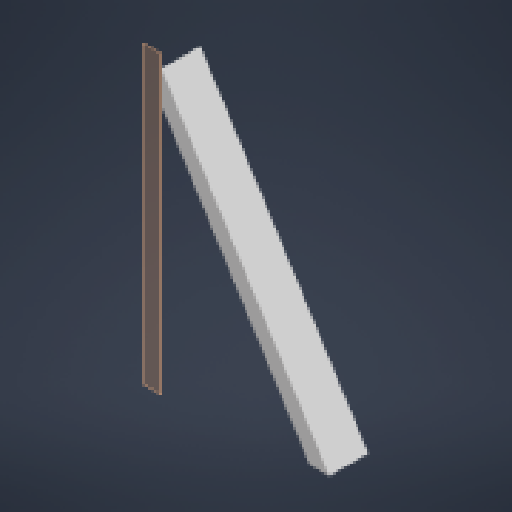
# Autodesk Inventor part: Side Connectors.2
Saved by Autodesk Inventor 2027 (Build 310192000, 192)
## iProperties
Created: 2026-10-18
Part Number: Side Connectors.2
Material: Generic
Document SubType Name: Modeling
Designer: lucas
Density: 1 g/cm^3
Appearance: Default
Author: lucas
Autodesk Inventor part; units mm, degrees
ref_plane "YZ Plane" through (0, 0, 0) normal (1, 0, 0) x (0, 1, 0)
ref_plane "XZ Plane" through (0, 0, 0) normal (0, 1, 0) x (-1, 0, 0)
ref_plane "XY Plane" through (0, 0, 0) normal (0, 0, 1) x (1, 0, 0)
ref_plane "Work Plane1" through (0, 0, 0) normal (0, 0, 1) x (1, 0, 0)
sketch "Sketch1" plane through (0, 0, 0) normal (0, 0, 1) x (1, 0, 0)
  line L0 (381, -609.6) -> (0, 0)
  line L1 (336.0707, -609.6) -> (0, -71.8869)
  line L2 (381, -609.6) -> (336.0707, -609.6)
  line L3 (0, -71.8869) -> (0, 0)
  dimension "d0" = 38.1
  constraints: 8 end point, 1 horizontal, 1 parallel, 1 vertical, 2 other
  measures "d0" distance between parallel lines of L1 L0
extrude "Extrusion1" add sketch "Sketch1" against normal blind 88.9
body "Solid1"
